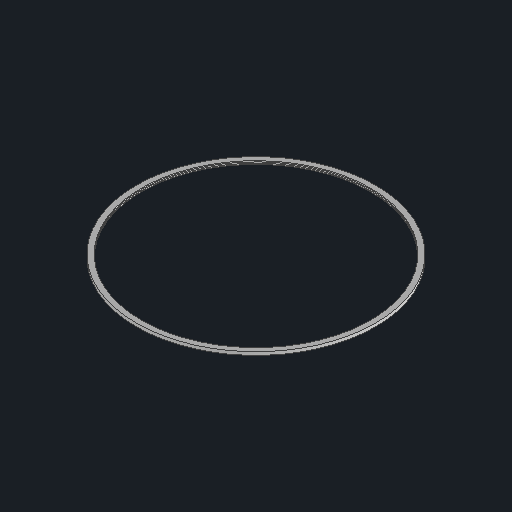
# Autodesk Inventor part: SealIn
Saved by Autodesk Inventor 2027.2 (Build 312334000, 334)
## iProperties
Created: 2026-11-16
Part Number: SealIn
Material: Generic
Document SubType Name: Modeling
Designer: Gasteng5
Density: 1 g/cm^3
Appearance: Default
Author: Gasteng5
Comments: Keltan-EPDM-black
Autodesk Inventor part; units mm, degrees
ref_plane "YZ Plane" through (0, 0, 0) normal (1, 0, 0) x (0, 1, 0)
ref_plane "XZ Plane" through (0, 0, 0) normal (0, 1, 0) x (-1, 0, 0)
ref_plane "XY Plane" through (0, 0, 0) normal (0, 0, 1) x (1, 0, 0)
sketch "Sketch1" plane through (0, 0, 0) normal (1, 0, 0) x (0, 1, 0)
  line L0 (0, 0) -> (-230, 0) construction
  line L1 (-235, -3.15) -> (-225, -3.15)
  line L2 (-225, 3.15) -> (-235, 3.15)
  line L3 (-235, 3.15) -> (-235, -3.15)
  line L4 (-235, -3.15) -> (-225, 3.15) construction
  line L5 (-225, -3.15) -> (-235, 3.15) construction
  line L6 (-225, -3.15) -> (-225, -1.15)
  line L7 (-225, -1.15) -> (-231.8254, -1.15)
  line L8 (-231.8254, 0) -> (-231.8254, -1.15)
  line L9 (-235, 0) -> (-37.5, 0)
  line L10 (-225, 1.15) -> (-231.8254, 1.15)
  line L11 (-231.8254, 0) -> (-231.8254, 1.15)
  line L12 (-225, 3.15) -> (-225, 1.15)
  line L13 (0, -4.41) -> (0, 4.41) projected
  dimension "d4" = 6.3
  dimension "d7" = 2
  dimension "d8" = 225
  dimension "d11" = 235
  constraints: 26 end point, 3 midpoint, 3 parallel, 3 point on line, 2 horizontal, 2 symmetric about line, 2 vertical, 1 coincident, 1 perpendicular
  measures "d4" distance of L2.end L1.start
  measures "d7" distance of L1.end L6.end
  measures "d8" distance from line of L0.start L6
  measures "d11" distance from line of L0.start L3
revolve "Revolution1" add sketch "Sketch1" angle 360 about axis through (0, 0, -10) along (0, 0, 1)
equation "\"d8\" = 0.5 * BinnenDiaMeter"
equation "\"d11\" = 0.5 * BuitenDiaMeter"
equation "\"BinnenDiaMeter\" = 450"
equation "\"BuitenDiaMeter\" = 470"
body "Solid1"
